StepDown (Autodesk Fusion 360 design; units mm, degrees)
part number: 2026-04-30-00-03-14-785
Autodesk Fusion 360 part; units mm, degrees
sketch "Sketch1" plane through (0, 0, 0) normal (0, 0, 1) x (1, 0, 0)
  line L0 (-62, 35.5) -> (62, 35.5)
  line L1 (62, 35.5) -> (62, -35.5)
  line L2 (62, -35.5) -> (-62, -35.5)
  line L3 (-62, -35.5) -> (-62, 35.5)
  line L4 (1.75, 0) -> (22.5, 0)
  line L5 (0, 1.75) -> (0, 22.5)
  circle A0 centre (-59, 32.5) radius 1.5
  circle A1 centre (-59, -32.5) radius 1.5
  circle A2 centre (59, -32.5) radius 1.5
  circle A3 centre (59, 32.5) radius 1.5
  dimension "d1" = 124
  dimension "d2" = 71
  dimension "d3" = 3
  dimension "d4" = 3
  dimension "d5" = 3
  dimension "d6" = 3
  dimension "d7" = 3
  dimension "d8" = 3
  dimension "d9" = 3
  dimension "d10" = 3
  dimension "d11" = 3
  dimension "d12" = 3
  dimension "d13" = 3
  dimension "d14" = 3
  constraint horizontal L0
  constraint vertical L1
  constraint horizontal L2
  constraint vertical L3
  constraint symmetric L0 L2 L4
  constraint symmetric L1 L3 L5
  measures "d1" distance of L0.start L0.end
  measures "d2" distance of L0.end L1.end
  measures "d3" diameter of A0
  measures "d4" distance of L0 A0.centre
  measures "d5" distance of L3 A0.centre
  measures "d6" diameter of A1
  measures "d7" distance of L3 A1.centre
  measures "d8" distance of L2 A1.centre
  measures "d9" diameter of A2
  measures "d10" distance of L1 A2.centre
  measures "d11" distance of L2 A2.centre
  measures "d12" diameter of A3
  measures "d13" distance of L0 A3.centre
  measures "d14" distance of L1 A3.centre
extrude "Extrude1" add sketch "Sketch1" along normal blind 2 makes body 1
sketch "Sketch2" plane through (0, 0, 2) normal (0, 0, 1) x (-1, 0, 0)
  circle A0 centre (-59, 32.5) radius 1.5
  circle A1 centre (-59, -32.5) radius 1.5
  circle A2 centre (59, -32.5) radius 1.5
  circle A3 centre (59, 32.5) radius 1.5
  line L0 (62, 35.5) -> (-62, 35.5)
  line L1 (-62, 35.5) -> (-62, -35.5)
  line L2 (-62, -35.5) -> (62, -35.5)
  line L3 (62, -35.5) -> (62, 35.5)
  circle A4 centre (-31.7917, -2.1313) radius 9
  circle A5 centre (-30, -25) radius 9
  circle A6 centre (-50, -25) radius 9
  line L4 (-2.4273, -14.327) -> (41.5009, -14.327)
  line L5 (41.5009, -14.327) -> (41.5009, -33.9822)
  line L6 (41.5009, -33.9822) -> (-2.4273, -33.9822)
  line L7 (-2.4273, -33.9822) -> (-2.4273, -14.327)
  circle A7 centre (49.9077, -23.5626) radius 9
  dimension "d17" = 18
  dimension "d18" = 18
  dimension "d19" = 18
  dimension "d20" = 18
  constraint horizontal L4
  constraint vertical L5
  constraint horizontal L6
  constraint vertical L7
  measures "d17" diameter of A4
  measures "d18" diameter of A6
  measures "d19" diameter of A5
  measures "d20" diameter of A7
extrude "Extrude2" add sketch "Sketch2" along normal blind 35 contours A4 | A5 | A6 | L5 A7 picked at (47.2712, -23.1257) bodies 1
extrude "Extrude3" add sketch "Sketch2" along normal blind 40 separate body contours L4 L5 L6 L7 A7 makes body 2
